Autodesk Inventor part; units mm, degrees
(part 2 of 3)
sketch "Sketch6" plane through (0, 7, 0) normal (0, 1, 0) x (1, 0, 0)
  line L0 (449, 226) -> (-449, 226) projected
  line L1 (-456, 219) -> (-456, -419) projected
  line L2 (456, -419) -> (456, 219) projected
  line L3 (-449, -426) -> (449, -426) projected
  arc A0 (-456, -419) -> (-449, -426) centre (-449, -419) ccw projected
  arc A1 (449, -426) -> (456, -419) centre (449, -419) ccw projected
  arc A2 (456, 219) -> (449, 226) centre (449, 219) ccw projected
  arc A3 (-449, 226) -> (-456, 219) centre (-449, 219) ccw projected
  line L4 (-449, 219) -> (449, 219)
  line L5 (449, 219) -> (449, -419)
  line L6 (449, -419) -> (-449, -419)
  line L7 (-449, -419) -> (-449, 219)
  line L8 (-449, 226) -> (-456, 226)
  line L9 (-456, 226) -> (-456, 219)
  line L10 (449, 226) -> (456, 226)
  line L11 (456, 226) -> (456, 219)
  line L12 (456, -419) -> (456, -426)
  line L13 (456, -426) -> (449, -426)
  line L14 (-456, -419) -> (-456, -426)
  line L15 (-456, -426) -> (-449, -426)
  line L16 (-456, 226) -> (-407.85, 226)
  line L17 (-407.85, 226) -> (-407.85, 219)
  line L18 (-407.85, 219) -> (-456, 219)
  line L19 (-456, 219) -> (-456, 226)
  line L20 (-407.85, 226) -> (-360.15, 226)
  line L21 (-360.15, 226) -> (-360.15, 219)
  line L22 (-360.15, 219) -> (-407.85, 219)
  line L23 (-407.85, 219) -> (-407.85, 226)
  line L24 (-264.15, 226) -> (-264.15, 219)
  line L25 (-311.85, 226) -> (-311.85, 219)
  line L26 (-168.15, 226) -> (-168.15, 219)
  line L27 (-215.85, 226) -> (-215.85, 219)
  line L28 (-72.15, 226) -> (-72.15, 219)
  line L29 (-119.85, 226) -> (-119.85, 219)
  line L30 (23.85, 226) -> (23.85, 219)
  line L31 (-23.85, 226) -> (-23.85, 219)
  line L32 (119.85, 226) -> (119.85, 219)
  line L33 (72.15, 226) -> (72.15, 219)
  line L34 (215.85, 226) -> (215.85, 219)
  line L35 (168.15, 226) -> (168.15, 219)
  line L36 (311.85, 226) -> (311.85, 219)
  line L37 (264.15, 226) -> (264.15, 219)
  line L38 (407.85, 226) -> (407.85, 219)
  line L39 (360.15, 226) -> (360.15, 219)
  line L40 (-449, -100) -> (456, -100) construction
  line L41 (-407.85, -426) -> (-407.85, -419)
  line L42 (-360.15, -426) -> (-360.15, -419)
  line L43 (-264.15, -426) -> (-264.15, -419)
  line L44 (-311.85, -426) -> (-311.85, -419)
  line L45 (-168.15, -426) -> (-168.15, -419)
  line L46 (-215.85, -426) -> (-215.85, -419)
  line L47 (-72.15, -426) -> (-72.15, -419)
  line L48 (-119.85, -426) -> (-119.85, -419)
  line L49 (23.85, -426) -> (23.85, -419)
  line L50 (-23.85, -426) -> (-23.85, -419)
  line L51 (119.85, -426) -> (119.85, -419)
  line L52 (72.15, -426) -> (72.15, -419)
  line L53 (215.85, -426) -> (215.85, -419)
  line L54 (168.15, -426) -> (168.15, -419)
  line L55 (311.85, -426) -> (311.85, -419)
  line L56 (264.15, -426) -> (264.15, -419)
  line L57 (407.85, -426) -> (407.85, -419)
  line L58 (360.15, -426) -> (360.15, -419)
  line L59 (-456, 226) -> (-449, 226)
  line L60 (-449, 226) -> (-449, 199.77)
  line L61 (-449, 199.77) -> (-456, 199.77)
  line L62 (-456, 199.77) -> (-456, 226)
  line L63 (-449, 199.77) -> (-456, 199.77)
  line L64 (-456, 199.77) -> (-456, 173.99)
  line L65 (-456, 173.99) -> (-449, 173.99)
  line L66 (-449, 173.99) -> (-449, 199.77)
  line L67 (-449, 147.61) -> (-456, 147.61)
  line L68 (-456, 121.83) -> (-449, 121.83)
  line L69 (-449, 95.45) -> (-456, 95.45)
  line L70 (-456, 69.67) -> (-449, 69.67)
  line L71 (-449, 43.29) -> (-456, 43.29)
  line L72 (-456, 17.51) -> (-449, 17.51)
  line L73 (-449, -8.87) -> (-456, -8.87)
  line L74 (-456, -34.65) -> (-449, -34.65)
  line L75 (-449, -61.03) -> (-456, -61.03)
  line L76 (-456, -86.81) -> (-449, -86.81)
  line L77 (-449, -113.19) -> (-456, -113.19)
  line L78 (-456, -138.97) -> (-449, -138.97)
  line L79 (-449, -165.35) -> (-456, -165.35)
  line L80 (-456, -191.13) -> (-449, -191.13)
  line L81 (-449, -217.51) -> (-456, -217.51)
  line L82 (-456, -243.29) -> (-449, -243.29)
  line L83 (-449, -269.67) -> (-456, -269.67)
  line L84 (-456, -295.45) -> (-449, -295.45)
  line L85 (-449, -321.83) -> (-456, -321.83)
  line L86 (-456, -347.61) -> (-449, -347.61)
  line L87 (-449, -373.99) -> (-456, -373.99)
  line L88 (-456, -399.77) -> (-449, -399.77)
  line L89 (0, 226) -> (0, -426) construction
  line L90 (449, 199.77) -> (456, 199.77)
  line L91 (456, 173.99) -> (449, 173.99)
  line L92 (449, 147.61) -> (456, 147.61)
  line L93 (456, 121.83) -> (449, 121.83)
  line L94 (449, 95.45) -> (456, 95.45)
  line L95 (456, 69.67) -> (449, 69.67)
  line L96 (449, 43.29) -> (456, 43.29)
  line L97 (456, 17.51) -> (449, 17.51)
  line L98 (449, -8.87) -> (456, -8.87)
  line L99 (456, -34.65) -> (449, -34.65)
  line L100 (449, -61.03) -> (456, -61.03)
  line L101 (456, -86.81) -> (449, -86.81)
  line L102 (449, -113.19) -> (456, -113.19)
  line L103 (456, -138.97) -> (449, -138.97)
  line L104 (449, -165.35) -> (456, -165.35)
  line L105 (456, -191.13) -> (449, -191.13)
  line L106 (449, -217.51) -> (456, -217.51)
  line L107 (456, -243.29) -> (449, -243.29)
  line L108 (449, -269.67) -> (456, -269.67)
  line L109 (456, -295.45) -> (449, -295.45)
  line L110 (449, -321.83) -> (456, -321.83)
  line L111 (456, -347.61) -> (449, -347.61)
  line L112 (449, -373.99) -> (456, -373.99)
  line L113 (456, -399.77) -> (449, -399.77)
  point P0 (0, 0)
  dimension "d424" = 7
  dimension "d425" = 912
  dimension "d426" = 652
  dimension "d427" = 48.15
  dimension "d428" = 47.7
  dimension "d431" = 96
  dimension "d436" = 26.23
  dimension "d437" = 25.78
  dimension "d440" = 52.16
  constraints: 212 end point, 84 symmetric about line, 46 parallel, 44 vertical alignment, 32 horizontal alignment, 7 perpendicular, 6 tangent, 5 horizontal, 2 point on line, 2 vertical, 24 other
  measures "d425" distance of L10.end L8.end
  measures "d426" distance of L12.end L10.end
  measures "d427" distance of L17.end L18.end
  measures "d428" distance between parallel lines of L17 L21
  measures "d431" distance of L20.end L24.start
  measures "d436" distance between parallel lines of L8 L61
  measures "d437" distance between parallel lines of L61 L65
  measures "d440" distance of L60.end L67.start
extrude "Extrusion8" cut sketch "Sketch6" against normal through all contours A2 L2 L90 L5 L4 L38 L0 | L39 L4 L36 L0 | L2 L92 L5 L91 | L37 L4 L34 L0 | L2 L94 L5 L93 | L35 L4 L32 L0 | L2 L96 L5 L95 | L33 L4 L30 L0 | L2 L98 L5 L97 | L31 L4 L28 L0 | L2 L100 L5 L99 | L29 L4 L26 L0 | L2 L102 L5 L101 | L27 L4 L24 L0 | L2 L104 L5 L103 | L25 L4 L21 L0 | L2 L106 L5 L105 | L17 L4 L60 L0 | L60 L18 A3 | L2 L108 L5 L107 | L18 L7 L61 L1 | L2 L110 L5 L109 | L65 L7 L67 L1 | L2 L112 L5 L111 | L68 L7 L69 L1 | L2 A1 L3 L57 L6 L5 L113 | L70 L7 L71 L1 | L72 L7 L73 L1 | L3 L55 L6 L58 | L74 L7 L75 L1 | L3 L53 L6 L56 | L76 L7 L77 L1 | L3 L51 L6 L54 | L78 L7 L79 L1 | L3 L49 L6 L52 | L80 L7 L81 L1 | L3 L47 L6 L50 | L82 L7 L83 L1 | L3 L45 L6 L48 | L84 L7 L85 L1 | L3 L43 L6 L46 | L86 L7 L87 L1 | L3 L42 L6 L44 | L88 L7 L6 L41 L3 A0 L1
fillet "Fillet2" radius 7 4 edges at (449, 3.5, -219) (449, 3.5, 419) (-449, 3.5, -219) (-449, 3.5, 419)
sketch "Sketch8" plane through (0, 7, 0) normal (0, 1, 0) x (1, 0, 0)
  circle A0 centre (126, -281.2169) radius 1.6 projected
  circle A1 centre (36.5, -281.7169) radius 1.575 projected
  circle A2 centre (127, -371.2169) radius 1.575 projected
  circle A3 centre (35.5, -371.2169) radius 1.575 projected
  circle A4 centre (8.08, -301.5) radius 1 projected
  circle A5 centre (-51, -301.5) radius 1 projected
  circle A6 centre (-51, -374.5) radius 1 projected
  circle A7 centre (8.08, -374.5) radius 1 projected
  circle A8 centre (-107.9098, -322.9439) radius 1.75 projected
  circle A9 centre (-145.2893, -322.9439) radius 1.75 projected
  circle A10 centre (-145.2893, -359.6857) radius 1.75 projected
  circle A11 centre (-107.9098, -359.6857) radius 1.75 projected
  arc A12 (-172.603, -348.9) -> (-172.603, -353.4) centre (-172.603, -351.15) ccw projected
  arc A13 (-259.703, -353.4) -> (-259.703, -348.9) centre (-259.703, -351.15) ccw projected
  line L0 (-259.703, -353.4) -> (-264.153, -353.4) projected
  line L1 (-259.703, -348.9) -> (-264.153, -348.9) projected
  arc A14 (-294.103, -348.9) -> (-294.103, -353.4) centre (-294.103, -351.15) ccw projected
  line L2 (-289.653, -348.9) -> (-294.103, -348.9) projected
  line L3 (-294.103, -353.4) -> (-289.653, -353.4) projected
  line L4 (-168.153, -348.9) -> (-172.603, -348.9) projected
  line L5 (-172.603, -353.4) -> (-168.153, -353.4) projected
  line L6 (-381.203, -348.9) -> (-385.653, -348.9) projected
  arc A15 (-381.203, -353.4) -> (-381.203, -348.9) centre (-381.203, -351.15) ccw projected
  line L7 (-381.203, -353.4) -> (-385.653, -353.4) projected
  line L8 (-264.153, -348.9) -> (-264.153, -353.4)
  line L9 (-289.653, -353.4) -> (-289.653, -348.9)
  line L10 (-168.153, -348.9) -> (-168.153, -353.4)
  line L11 (-385.653, -348.9) -> (-385.653, -353.4)
  circle A16 centre (11, -29.5) radius 2.5 projected
  circle A17 centre (11, 29.5) radius 2.5 projected
  circle A18 centre (276, 65.5) radius 2 projected
  circle A19 centre (256, 65.5) radius 2 projected
  point P0 (0, 0)
  constraints: 8 end point, 2 parallel, 2 vertical
extrude "Extrusion9" cut sketch "Sketch8" against normal through all
sketch "Sketch9" plane through (0, 7, 0) normal (0, 1, 0) x (1, 0, 0)
  line L0 (-456, 95.45) -> (-456, 69.67) projected
  line L1 (-456, 89) -> (456, 89)
  line L2 (456, 69.67) -> (456, 95.45) projected
  line L3 (407.85, 226) -> (360.15, 226) projected
  line L4 (456, 69.67) -> (456, 95.45) projected
  line L5 (-456, 82) -> (456, 82)
  line L6 (-449, 89) -> (-449, 82)
  line L7 (-449, 121.83) -> (-449, 95.45) projected
  line L8 (449, 82) -> (449, 89)
  line L9 (449, 95.45) -> (449, 121.83) projected
  line L10 (449, 82) -> (413.08, 82)
  line L11 (413.08, 82) -> (413.08, 89)
  line L12 (413.08, 89) -> (449, 89)
  line L13 (449, 89) -> (449, 82)
  line L14 (377.16, 82) -> (377.16, 89)
  line L15 (341.24, 82) -> (341.24, 89)
  line L16 (305.32, 82) -> (305.32, 89)
  line L17 (269.4, 82) -> (269.4, 89)
  line L18 (233.48, 82) -> (233.48, 89)
  line L19 (197.56, 82) -> (197.56, 89)
  line L20 (161.64, 82) -> (161.64, 89)
  line L21 (125.72, 82) -> (125.72, 89)
  line L22 (89.8, 82) -> (89.8, 89)
  line L23 (53.88, 82) -> (53.88, 89)
  line L24 (17.96, 82) -> (17.96, 89)
  line L25 (-17.96, 82) -> (-17.96, 89)
  line L26 (-53.88, 82) -> (-53.88, 89)
  line L27 (-89.8, 82) -> (-89.8, 89)
  line L28 (-125.72, 82) -> (-125.72, 89)
  line L29 (-161.64, 82) -> (-161.64, 89)
  line L30 (-197.56, 82) -> (-197.56, 89)
  line L31 (-233.48, 82) -> (-233.48, 89)
  line L32 (-269.4, 82) -> (-269.4, 89)
  line L33 (-305.32, 82) -> (-305.32, 89)
  line L34 (-341.24, 82) -> (-341.24, 89)
  line L35 (-377.16, 82) -> (-377.16, 89)
  line L36 (-413.08, 82) -> (-413.08, 89)
  line L37 (-449, 82) -> (-449, 89)
  line L38 (449, -189) -> (-449, -189)
  line L39 (-449, -189) -> (-449, -182)
  line L40 (-449, -182) -> (449, -182)
  line L41 (449, -182) -> (449, -189)
  line L42 (-449, -191.13) -> (-449, -217.51) projected
  line L43 (449, -217.51) -> (449, -191.13) projected
  line L44 (360.15, -426) -> (407.85, -426) projected
  line L45 (449, -189) -> (413.08, -189)
  line L46 (413.08, -189) -> (413.08, -182)
  line L47 (413.08, -182) -> (449, -182)
  line L48 (449, -182) -> (449, -189)
  line L49 (377.16, -189) -> (377.16, -182)
  line L50 (341.24, -189) -> (341.24, -182)
  line L51 (305.32, -189) -> (305.32, -182)
  line L52 (269.4, -189) -> (269.4, -182)
  line L53 (233.48, -189) -> (233.48, -182)
  line L54 (197.56, -189) -> (197.56, -182)
  line L55 (161.64, -189) -> (161.64, -182)
  line L56 (125.72, -189) -> (125.72, -182)
  line L57 (89.8, -189) -> (89.8, -182)
  line L58 (53.88, -189) -> (53.88, -182)
  line L59 (17.96, -189) -> (17.96, -182)
  line L60 (-17.96, -189) -> (-17.96, -182)
  line L61 (-53.88, -189) -> (-53.88, -182)
  line L62 (-89.8, -189) -> (-89.8, -182)
  line L63 (-125.72, -189) -> (-125.72, -182)
  line L64 (-161.64, -189) -> (-161.64, -182)
  line L65 (-197.56, -189) -> (-197.56, -182)
  line L66 (-233.48, -189) -> (-233.48, -182)
  line L67 (-269.4, -189) -> (-269.4, -182)
  line L68 (-305.32, -189) -> (-305.32, -182)
  line L69 (-341.24, -189) -> (-341.24, -182)
  line L70 (-377.16, -189) -> (-377.16, -182)
  line L71 (-413.08, -189) -> (-413.08, -182)
  line L72 (-449, -189) -> (-449, -182)
  point P0 (0, 0)
  point P1 (-449, 85.5)
  point P2 (-449, 108.64)
  point P3 (449, 85.5)
  point P4 (449, 108.64)
  point P5 (-449, -204.32)
  point P6 (-449, -185.5)
  point P7 (449, -185.5)
  point P8 (449, -204.32)
  dimension "d503" = 7
  dimension "d512" = 7
  dimension "d502" = 137
  dimension "d504" = 35.92
  dimension "d507" = 35.92
  dimension "d513" = 237
  dimension "d514" = 35.92
  dimension "d517" = 35.92
  constraints: 120 end point, 96 horizontal alignment, 53 parallel, 8 midpoint, 4 vertical, 4 vertical alignment, 2 horizontal, 2 perpendicular, 2 point on line, 18 other
  measures "d504" distance of L11.end L12.end
  measures "d507" distance of L10.end L14.start
  measures "d514" distance of L46.end L47.end
  measures "d517" distance of L45.end L49.start
extrude "Extrusion10" cut sketch "Sketch9" against normal through all contours L1 L36 L5 L6 | L1 L34 L5 L35 | L1 L32 L5 L33 | L1 L30 L5 L31 | L1 L28 L5 L29 | L1 L26 L5 L27 | L1 L24 L5 L25 | L1 L22 L5 L23 | L1 L20 L5 L21 | L1 L18 L5 L19 | L1 L16 L5 L17 | L1 L14 L5 L15 | L1 L8 L5 L11 | L38 L46 L40 L41 | L38 L50 L40 L49 | L38 L52 L40 L51 | L38 L54 L40 L53 | L38 L56 L40 L55 | L38 L58 L40 L57 | L38 L60 L40 L59 | L38 L62 L40 L61 | L38 L64 L40 L63 | L38 L66 L40 L65 | L38 L68 L40 L67 | L38 L70 L40 L69 | L38 L39 L40 L71
sketch "Sketch10" plane through (0, 7, 0) normal (0, 1, 0) x (1, 0, 0)
  line L0 (269.4, -182) -> (269.4, -189) projected
  line L1 (269.4, -189) -> (305.32, -189) projected
  line L2 (305.32, -189) -> (305.32, -182) projected
  line L3 (305.32, -182) -> (269.4, -182) projected
  line L4 (-17.96, -182) -> (-17.96, -189) projected
  line L5 (-17.96, -189) -> (17.96, -189) projected
  line L6 (17.96, -189) -> (17.96, -182) projected
  line L7 (17.96, -182) -> (-17.96, -182) projected
  line L8 (-305.32, -182) -> (-305.32, -189) projected
  line L9 (-305.32, -189) -> (-269.4, -189) projected
  line L10 (-269.4, -189) -> (-269.4, -182) projected
  line L11 (-269.4, -182) -> (-305.32, -182) projected
  line L12 (341.24, 89) -> (341.24, 82) projected
  line L13 (341.24, 82) -> (377.16, 82) projected
  line L14 (377.16, 82) -> (377.16, 89) projected
  line L15 (377.16, 89) -> (341.24, 89) projected
  line L16 (53.88, 89) -> (53.88, 82) projected
  line L17 (53.88, 82) -> (89.8, 82) projected
  line L18 (89.8, 82) -> (89.8, 89) projected
  line L19 (89.8, 89) -> (53.88, 89) projected
  line L20 (-233.48, 89) -> (-233.48, 82) projected
  line L21 (-233.48, 82) -> (-197.56, 82) projected
  line L22 (-197.56, 82) -> (-197.56, 89) projected
  line L23 (-197.56, 89) -> (-233.48, 89) projected
  line L24 (-413.08, 82) -> (-413.08, 89) projected
  line L25 (-413.08, 89) -> (-449, 89) projected
  line L26 (-449, 89) -> (-449, 82) projected
  line L27 (-449, 82) -> (-413.08, 82) projected
  line L28 (-161.64, 89) -> (-161.64, 82) projected
  line L29 (-161.64, 82) -> (-125.72, 82) projected
  line L30 (-125.72, 82) -> (-125.72, 89) projected
  line L31 (-125.72, 89) -> (-161.64, 89) projected
  line L32 (125.72, 89) -> (125.72, 82) projected
  line L33 (125.72, 82) -> (161.64, 82) projected
  line L34 (161.64, 82) -> (161.64, 89) projected
  line L35 (161.64, 89) -> (125.72, 89) projected
  line L36 (413.08, 89) -> (413.08, 82) projected
  line L37 (413.08, 82) -> (449, 82) projected
  line L38 (449, 82) -> (449, 89) projected
  line L39 (449, 89) -> (413.08, 89) projected
  line L40 (-233.48, -182) -> (-233.48, -189) projected
  line L41 (-233.48, -189) -> (-197.56, -189) projected
  line L42 (-197.56, -189) -> (-197.56, -182) projected
  line L43 (-197.56, -182) -> (-233.48, -182) projected
  line L44 (53.88, -182) -> (53.88, -189) projected
  line L45 (53.88, -189) -> (89.8, -189) projected
  line L46 (89.8, -189) -> (89.8, -182) projected
  line L47 (89.8, -182) -> (53.88, -182) projected
  line L48 (341.24, -182) -> (341.24, -189) projected
  line L49 (341.24, -189) -> (377.16, -189) projected
  line L50 (377.16, -189) -> (377.16, -182) projected
  line L51 (377.16, -182) -> (341.24, -182) projected
  line L52 (197.56, -182) -> (197.56, -189) projected
  line L53 (197.56, -189) -> (233.48, -189) projected
  line L54 (233.48, -189) -> (233.48, -182) projected
  line L55 (233.48, -182) -> (197.56, -182) projected
  line L56 (-89.8, -182) -> (-89.8, -189) projected
  line L57 (-89.8, -189) -> (-53.88, -189) projected
  line L58 (-53.88, -189) -> (-53.88, -182) projected
  line L59 (-53.88, -182) -> (-89.8, -182) projected
  line L60 (-377.16, -182) -> (-377.16, -189) projected
  line L61 (-377.16, -189) -> (-341.24, -189) projected
  line L62 (-341.24, -189) -> (-341.24, -182) projected
  line L63 (-341.24, -182) -> (-377.16, -182) projected
  line L64 (269.4, 89) -> (269.4, 82) projected
  line L65 (269.4, 82) -> (305.32, 82) projected
  line L66 (305.32, 82) -> (305.32, 89) projected
  line L67 (305.32, 89) -> (269.4, 89) projected
  line L68 (-17.96, 89) -> (-17.96, 82) projected
  line L69 (-17.96, 82) -> (17.96, 82) projected
  line L70 (17.96, 82) -> (17.96, 89) projected
  line L71 (17.96, 89) -> (-17.96, 89) projected
  line L72 (-305.32, 89) -> (-305.32, 82) projected
  line L73 (-305.32, 82) -> (-269.4, 82) projected
  line L74 (-269.4, 82) -> (-269.4, 89) projected
  line L75 (-269.4, 89) -> (-305.32, 89) projected
  line L76 (-377.16, 89) -> (-377.16, 82) projected
  line L77 (-377.16, 82) -> (-341.24, 82) projected
  line L78 (-341.24, 82) -> (-341.24, 89) projected
  line L79 (-341.24, 89) -> (-377.16, 89) projected
  line L80 (-89.8, 89) -> (-89.8, 82) projected
  line L81 (-89.8, 82) -> (-53.88, 82) projected
  line L82 (-53.88, 82) -> (-53.88, 89) projected
  line L83 (-53.88, 89) -> (-89.8, 89) projected
  line L84 (197.56, 89) -> (197.56, 82) projected
  line L85 (197.56, 82) -> (233.48, 82) projected
  line L86 (233.48, 82) -> (233.48, 89) projected
  line L87 (233.48, 89) -> (197.56, 89) projected
  line L88 (-413.08, -189) -> (-413.08, -182) projected
  line L89 (-413.08, -182) -> (-449, -182) projected
  line L90 (-449, -182) -> (-449, -189) projected
  line L91 (-449, -189) -> (-413.08, -189) projected
  line L92 (-161.64, -182) -> (-161.64, -189) projected
  line L93 (-161.64, -189) -> (-125.72, -189) projected
  line L94 (-125.72, -189) -> (-125.72, -182) projected
  line L95 (-125.72, -182) -> (-161.64, -182) projected
  line L96 (125.72, -182) -> (125.72, -189) projected
  line L97 (125.72, -189) -> (161.64, -189) projected
  line L98 (161.64, -189) -> (161.64, -182) projected
  line L99 (161.64, -182) -> (125.72, -182) projected
  line L100 (413.08, -182) -> (413.08, -189) projected
  line L101 (413.08, -189) -> (449, -189) projected
  line L102 (449, -189) -> (449, -182) projected
  line L103 (449, -182) -> (413.08, -182) projected
  circle A0 centre (127, -371.2169) radius 1.575 projected
  circle A1 centre (8.08, -374.5) radius 1 projected
  circle A2 centre (-107.9098, -359.6857) radius 1.75 projected
  line L104 (-168.153, -348.9) -> (-172.603, -348.9) projected
  arc A3 (-172.603, -348.9) -> (-172.603, -353.4) centre (-172.603, -351.15) ccw projected
  line L105 (-172.603, -353.4) -> (-168.153, -353.4) projected
  line L106 (-168.153, -353.4) -> (-168.153, -348.9) projected
  arc A4 (-381.203, -353.4) -> (-381.203, -348.9) centre (-381.203, -351.15) ccw projected
  line L107 (-381.203, -348.9) -> (-385.653, -348.9) projected
  line L108 (-385.653, -348.9) -> (-385.653, -353.4) projected
  line L109 (-385.653, -353.4) -> (-381.203, -353.4) projected
  circle A5 centre (-145.2893, -359.6857) radius 1.75 projected
  circle A6 centre (-51, -374.5) radius 1 projected
  circle A7 centre (35.5, -371.2169) radius 1.575 projected
  circle A8 centre (11, 29.5) radius 2.5 projected
  circle A9 centre (126, -281.2169) radius 1.6 projected
  circle A10 centre (8.08, -301.5) radius 1 projected
  circle A11 centre (-107.9098, -322.9439) radius 1.75 projected
  arc A12 (-259.703, -353.4) -> (-259.703, -348.9) centre (-259.703, -351.15) ccw projected
  line L110 (-259.703, -348.9) -> (-264.153, -348.9) projected
  line L111 (-264.153, -348.9) -> (-264.153, -353.4) projected
  line L112 (-264.153, -353.4) -> (-259.703, -353.4) projected
  arc A13 (-294.103, -348.9) -> (-294.103, -353.4) centre (-294.103, -351.15) ccw projected
  line L113 (-294.103, -353.4) -> (-289.653, -353.4) projected
  line L114 (-289.653, -353.4) -> (-289.653, -348.9) projected
  line L115 (-289.653, -348.9) -> (-294.103, -348.9) projected
  circle A14 centre (-145.2893, -322.9439) radius 1.75 projected
  circle A15 centre (-51, -301.5) radius 1 projected
  circle A16 centre (36.5, -281.7169) radius 1.575 projected
  circle A17 centre (11, -29.5) radius 2.5 projected
  line L116 (-407.85, 219) -> (-407.85, 226) projected
  line L117 (-407.85, 226) -> (-360.15, 226) projected
  line L118 (-360.15, 226) -> (-360.15, 219) projected
  line L119 (-360.15, 219) -> (-311.85, 219) projected
  line L120 (-311.85, 219) -> (-311.85, 226) projected
  line L121 (-311.85, 226) -> (-264.15, 226) projected
  line L122 (-264.15, 226) -> (-264.15, 219) projected
  line L123 (-264.15, 219) -> (-215.85, 219) projected
  line L124 (-215.85, 219) -> (-215.85, 226) projected
  line L125 (-215.85, 226) -> (-168.15, 226) projected
  line L126 (-168.15, 226) -> (-168.15, 219) projected
  line L127 (-168.15, 219) -> (-119.85, 219) projected
  line L128 (-119.85, 219) -> (-119.85, 226) projected
  line L129 (-119.85, 226) -> (-72.15, 226) projected
  line L130 (-72.15, 226) -> (-72.15, 219) projected
  line L131 (-72.15, 219) -> (-23.85, 219) projected
  line L132 (-23.85, 219) -> (-23.85, 226) projected
  line L133 (-23.85, 226) -> (23.85, 226) projected
  line L134 (23.85, 226) -> (23.85, 219) projected
  line L135 (23.85, 219) -> (72.15, 219) projected
  line L136 (72.15, 219) -> (72.15, 226) projected
  line L137 (72.15, 226) -> (119.85, 226) projected
  line L138 (119.85, 226) -> (119.85, 219) projected
  line L139 (119.85, 219) -> (168.15, 219) projected
  line L140 (168.15, 219) -> (168.15, 226) projected
  line L141 (168.15, 226) -> (215.85, 226) projected
  line L142 (215.85, 226) -> (215.85, 219) projected
  line L143 (215.85, 219) -> (264.15, 219) projected
  line L144 (264.15, 219) -> (264.15, 226) projected
  line L145 (264.15, 226) -> (311.85, 226) projected
  line L146 (311.85, 226) -> (311.85, 219) projected
  line L147 (311.85, 219) -> (360.15, 219) projected
  line L148 (360.15, 219) -> (360.15, 226) projected
  line L149 (360.15, 226) -> (407.85, 226) projected
  line L150 (407.85, 226) -> (407.85, 219) projected
  line L151 (407.85, 219) -> (442, 219) projected
  arc A18 (449, 212) -> (442, 219) centre (442, 212) ccw projected
  line L152 (449, 212) -> (449, 199.77) projected
  line L153 (449, 199.77) -> (456, 199.77) projected
  line L154 (456, 199.77) -> (456, 173.99) projected
  line L155 (456, 173.99) -> (449, 173.99) projected
  line L156 (449, 173.99) -> (449, 147.61) projected
  line L157 (449, 147.61) -> (456, 147.61) projected
  line L158 (456, 147.61) -> (456, 121.83) projected
  line L159 (456, 121.83) -> (449, 121.83) projected
  line L160 (449, 121.83) -> (449, 95.45) projected
  line L161 (449, 95.45) -> (456, 95.45) projected
  line L162 (456, 95.45) -> (456, 69.67) projected
  line L163 (456, 69.67) -> (449, 69.67) projected
  line L164 (449, 69.67) -> (449, 43.29) projected
  line L165 (449, 43.29) -> (456, 43.29) projected
  line L166 (456, 43.29) -> (456, 17.51) projected
  line L167 (456, 17.51) -> (449, 17.51) projected
  line L168 (449, 17.51) -> (449, -8.87) projected
  line L169 (449, -8.87) -> (456, -8.87) projected
  line L170 (456, -8.87) -> (456, -34.65) projected
  line L171 (456, -34.65) -> (449, -34.65) projected
  line L172 (449, -34.65) -> (449, -61.03) projected
  line L173 (449, -61.03) -> (456, -61.03) projected
  line L174 (456, -61.03) -> (456, -86.81) projected
  line L175 (456, -86.81) -> (449, -86.81) projected
  line L176 (449, -86.81) -> (449, -113.19) projected
  line L177 (449, -113.19) -> (456, -113.19) projected
  line L178 (456, -113.19) -> (456, -138.97) projected
  line L179 (456, -138.97) -> (449, -138.97) projected
  line L180 (449, -138.97) -> (449, -165.35) projected
  line L181 (449, -165.35) -> (456, -165.35) projected
  line L182 (456, -165.35) -> (456, -191.13) projected
  line L183 (456, -191.13) -> (449, -191.13) projected
  line L184 (449, -191.13) -> (449, -217.51) projected
  line L185 (449, -217.51) -> (456, -217.51) projected
  line L186 (456, -217.51) -> (456, -243.29) projected
  line L187 (456, -243.29) -> (449, -243.29) projected
  line L188 (449, -243.29) -> (449, -269.67) projected
  line L189 (449, -269.67) -> (456, -269.67) projected
  line L190 (456, -269.67) -> (456, -295.45) projected
  line L191 (456, -295.45) -> (449, -295.45) projected
  line L192 (449, -295.45) -> (449, -321.83) projected
  line L193 (449, -321.83) -> (456, -321.83) projected
  line L194 (456, -321.83) -> (456, -347.61) projected
  line L195 (456, -347.61) -> (449, -347.61) projected
  line L196 (449, -347.61) -> (449, -373.99) projected
  line L197 (449, -373.99) -> (456, -373.99) projected
  line L198 (456, -373.99) -> (456, -399.77) projected
  line L199 (456, -399.77) -> (449, -399.77) projected
  line L200 (449, -399.77) -> (449, -412) projected
  arc A19 (442, -419) -> (449, -412) centre (442, -412) ccw projected
  line L201 (442, -419) -> (407.85, -419) projected
  line L202 (407.85, -419) -> (407.85, -426) projected
  line L203 (407.85, -426) -> (360.15, -426) projected
  line L204 (360.15, -426) -> (360.15, -419) projected
  line L205 (360.15, -419) -> (311.85, -419) projected
  line L206 (311.85, -419) -> (311.85, -426) projected
  line L207 (311.85, -426) -> (264.15, -426) projected
  line L208 (264.15, -426) -> (264.15, -419) projected
  line L209 (264.15, -419) -> (215.85, -419) projected
  line L210 (215.85, -419) -> (215.85, -426) projected
  line L211 (215.85, -426) -> (168.15, -426) projected
  line L212 (168.15, -426) -> (168.15, -419) projected
  line L213 (168.15, -419) -> (119.85, -419) projected
  line L214 (119.85, -419) -> (119.85, -426) projected
  line L215 (119.85, -426) -> (72.15, -426) projected
  line L216 (72.15, -426) -> (72.15, -419) projected
  line L217 (72.15, -419) -> (23.85, -419) projected
  line L218 (23.85, -419) -> (23.85, -426) projected
  line L219 (23.85, -426) -> (-23.85, -426) projected
  line L220 (-23.85, -426) -> (-23.85, -419) projected
  line L221 (-23.85, -419) -> (-72.15, -419) projected
  line L222 (-72.15, -419) -> (-72.15, -426) projected
  line L223 (-72.15, -426) -> (-119.85, -426) projected
  line L224 (-119.85, -426) -> (-119.85, -419) projected
  line L225 (-119.85, -419) -> (-168.15, -419) projected
  line L226 (-168.15, -419) -> (-168.15, -426) projected
  line L227 (-168.15, -426) -> (-215.85, -426) projected
  line L228 (-215.85, -426) -> (-215.85, -419) projected
  line L229 (-215.85, -419) -> (-264.15, -419) projected
  line L230 (-264.15, -419) -> (-264.15, -426) projected
  line L231 (-264.15, -426) -> (-311.85, -426) projected
  line L232 (-311.85, -426) -> (-311.85, -419) projected
  line L233 (-311.85, -419) -> (-360.15, -419) projected
  line L234 (-360.15, -419) -> (-360.15, -426) projected
  line L235 (-360.15, -426) -> (-407.85, -426) projected
  line L236 (-407.85, -426) -> (-407.85, -419) projected
  line L237 (-407.85, -419) -> (-442, -419) projected
  arc A20 (-449, -412) -> (-442, -419) centre (-442, -412) ccw projected
  line L238 (-449, -412) -> (-449, -399.77) projected
  line L239 (-449, -399.77) -> (-456, -399.77) projected
  line L240 (-456, -399.77) -> (-456, -373.99) projected
  line L241 (-456, -373.99) -> (-449, -373.99) projected
  line L242 (-449, -373.99) -> (-449, -347.61) projected
  line L243 (-449, -347.61) -> (-456, -347.61) projected
  line L244 (-456, -347.61) -> (-456, -321.83) projected
  line L245 (-456, -321.83) -> (-449, -321.83) projected
  line L246 (-449, -321.83) -> (-449, -295.45) projected
  line L247 (-449, -295.45) -> (-456, -295.45) projected
  line L248 (-456, -295.45) -> (-456, -269.67) projected
  line L249 (-456, -269.67) -> (-449, -269.67) projected
  line L250 (-449, -269.67) -> (-449, -243.29) projected
  line L251 (-449, -243.29) -> (-456, -243.29) projected
  line L252 (-456, -243.29) -> (-456, -217.51) projected
  line L253 (-456, -217.51) -> (-449, -217.51) projected
  line L254 (-449, -217.51) -> (-449, -191.13) projected
  line L255 (-449, -191.13) -> (-456, -191.13) projected
  line L256 (-456, -191.13) -> (-456, -165.35) projected
  line L257 (-456, -165.35) -> (-449, -165.35) projected
  line L258 (-449, -165.35) -> (-449, -138.97) projected
  line L259 (-449, -138.97) -> (-456, -138.97) projected
  line L260 (-456, -138.97) -> (-456, -113.19) projected
  line L261 (-456, -113.19) -> (-449, -113.19) projected
  line L262 (-449, -113.19) -> (-449, -86.81) projected
  line L263 (-449, -86.81) -> (-456, -86.81) projected
  line L264 (-456, -86.81) -> (-456, -61.03) projected
  line L265 (-456, -61.03) -> (-449, -61.03) projected
  line L266 (-449, -61.03) -> (-449, -34.65) projected
  line L267 (-449, -34.65) -> (-456, -34.65) projected
  line L268 (-456, -34.65) -> (-456, -8.87) projected
  line L269 (-456, -8.87) -> (-449, -8.87) projected
  line L270 (-449, -8.87) -> (-449, 17.51) projected
  line L271 (-449, 17.51) -> (-456, 17.51) projected
  line L272 (-456, 17.51) -> (-456, 43.29) projected
  line L273 (-456, 43.29) -> (-449, 43.29) projected
  line L274 (-449, 43.29) -> (-449, 69.67) projected
  line L275 (-449, 69.67) -> (-456, 69.67) projected
  line L276 (-456, 69.67) -> (-456, 95.45) projected
  line L277 (-456, 95.45) -> (-449, 95.45) projected
  line L278 (-449, 95.45) -> (-449, 121.83) projected
  line L279 (-449, 121.83) -> (-456, 121.83) projected
  line L280 (-456, 121.83) -> (-456, 147.61) projected
  line L281 (-456, 147.61) -> (-449, 147.61) projected
  line L282 (-449, 147.61) -> (-449, 173.99) projected
  line L283 (-449, 173.99) -> (-456, 173.99) projected
  line L284 (-456, 173.99) -> (-456, 199.77) projected
  line L285 (-456, 199.77) -> (-449, 199.77) projected
  line L286 (-449, 199.77) -> (-449, 212) projected
  arc A21 (-442, 219) -> (-449, 212) centre (-442, 212) ccw projected
  line L287 (-442, 219) -> (-407.85, 219) projected
  line L288 (-376, -308.5) -> (-76, -308.5) projected
  arc A22 (-76, -308.5) -> (-76, -283.5) centre (-76, -296) ccw projected
  line L289 (-76, -283.5) -> (-376, -283.5) projected
  arc A23 (-376, -283.5) -> (-376, -308.5) centre (-376, -296) ccw projected
  line L290 (151.5, -286) -> (151.5, -366) projected
  arc A24 (151.5, -366) -> (176.5, -366) centre (164, -366) ccw projected
  line L291 (176.5, -366) -> (176.5, -286) projected
  arc A25 (176.5, -286) -> (151.5, -286) centre (164, -286) ccw projected
  arc A26 (266, -25) -> (268, -23) centre (266, -23) ccw projected
  line L292 (268, -23) -> (268, 23) projected
  arc A27 (268, 23) -> (266, 25) centre (266, 23) ccw projected
  line L293 (266, 25) -> (107, 25) projected
  arc A28 (107, 25) -> (105, 23) centre (107, 23) ccw projected
  line L294 (105, 23) -> (105, -23) projected
  arc A29 (105, -23) -> (107, -25) centre (107, -23) ccw projected
  line L295 (107, -25) -> (266, -25) projected
  circle A30 centre (354.8, 16) radius 2.9 projected
  circle A31 centre (354.8, -16) radius 2.9 projected
  line L296 (204, -276) -> (201, -276) projected
  line L297 (201, -276) -> (201, -296) projected
  line L298 (201, -296) -> (204, -296) projected
  line L299 (204, -296) -> (204, -276) projected
  line L300 (-423, -316) -> (-426, -316) projected
  line L301 (-426, -316) -> (-426, -336) projected
  line L302 (-426, -336) -> (-423, -336) projected
  line L303 (-423, -336) -> (-423, -316) projected
  line L304 (9, -393) -> (9, -396) projected
  line L305 (9, -396) -> (57, -396) projected
  line L306 (57, -396) -> (57, -393) projected
  line L307 (57, -393) -> (9, -393) projected
  line L308 (-39, -259) -> (-39, -256) projected
  line L309 (-39, -256) -> (-87, -256) projected
  line L310 (-87, -256) -> (-87, -259) projected
  line L311 (-87, -259) -> (-39, -259) projected
  circle A32 centre (-67, 43) radius 2.5 projected
  circle A33 centre (-130, 43) radius 2.5 projected
  line L312 (46.5, 68) -> (51.5, 68) projected
  line L313 (51.5, 68) -> (51.5, 71) projected
  line L314 (51.5, 71) -> (46.5, 71) projected
  line L315 (46.5, 71) -> (46.5, 68) projected
  line L316 (3, 53) -> (6, 53) projected
  line L317 (6, 53) -> (6, 63) projected
  line L318 (6, 63) -> (3, 63) projected
  line L319 (3, 63) -> (3, 53) projected
  line L320 (46.25, -48) -> (56.25, -48) projected
  line L321 (56.25, -48) -> (56.25, -45) projected
  line L322 (56.25, -45) -> (46.25, -45) projected
  line L323 (46.25, -45) -> (46.25, -48) projected
  line L324 (46.25, -78) -> (46.25, -81) projected
  line L325 (46.25, -81) -> (56.25, -81) projected
  line L326 (56.25, -81) -> (56.25, -78) projected
  line L327 (56.25, -78) -> (46.25, -78) projected
  line L328 (61, -119.5) -> (61, -134.5) projected
  line L329 (61, -134.5) -> (64, -134.5) projected
  line L330 (64, -134.5) -> (64, -119.5) projected
  line L331 (64, -119.5) -> (61, -119.5) projected
  arc A34 (-406.25, 176) -> (-406, 176.25) centre (-406.25, 176.25) ccw projected
  line L332 (-406, 176.25) -> (-406, 195.75) projected
  arc A35 (-406, 195.75) -> (-406.25, 196) centre (-406.25, 195.75) ccw projected
  line L333 (-406.25, 196) -> (-425.75, 196) projected
  arc A36 (-425.75, 196) -> (-426, 195.75) centre (-425.75, 195.75) ccw projected
  line L334 (-426, 195.75) -> (-426, 176.25) projected
  arc A37 (-426, 176.25) -> (-425.75, 176) centre (-425.75, 176.25) ccw projected
  line L335 (-425.75, 176) -> (-406.25, 176) projected
  line L336 (-6.25, 196) -> (-25.75, 196) projected
  arc A38 (-25.75, 196) -> (-26, 195.75) centre (-25.75, 195.75) ccw projected
  line L337 (-26, 195.75) -> (-26, 176.25) projected
  arc A39 (-26, 176.25) -> (-25.75, 176) centre (-25.75, 176.25) ccw projected
  line L338 (-25.75, 176) -> (-6.25, 176) projected
  arc A40 (-6.25, 176) -> (-6, 176.25) centre (-6.25, 176.25) ccw projected
  line L339 (-6, 176.25) -> (-6, 195.75) projected
  arc A41 (-6, 195.75) -> (-6.25, 196) centre (-6.25, 195.75) ccw projected
  line L340 (2.5, -233.9) -> (5.5, -233.9) projected
  arc A42 (5.5, -233.9) -> (5.5, -228.1) centre (5.5, -231) ccw projected
  line L341 (5.5, -228.1) -> (2.5, -228.1) projected
  arc A43 (2.5, -228.1) -> (2.5, -233.9) centre (2.5, -231) ccw projected
  line L342 (-397.5, 183.1) -> (-394.5, 183.1) projected
  arc A44 (-394.5, 183.1) -> (-394.5, 188.9) centre (-394.5, 186) ccw projected
  line L343 (-394.5, 188.9) -> (-397.5, 188.9) projected
  arc A45 (-397.5, 188.9) -> (-397.5, 183.1) centre (-397.5, 186) ccw projected
  line L344 (-6.25, -221) -> (-25.75, -221) projected
  arc A46 (-25.75, -221) -> (-26, -221.25) centre (-25.75, -221.25) ccw projected
  line L345 (-26, -221.25) -> (-26, -240.75) projected
  arc A47 (-26, -240.75) -> (-25.75, -241) centre (-25.75, -240.75) ccw projected
  line L346 (-25.75, -241) -> (-6.25, -241) projected
  arc A48 (-6.25, -241) -> (-6, -240.75) centre (-6.25, -240.75) ccw projected
  line L347 (-6, -240.75) -> (-6, -221.25) projected
  arc A49 (-6, -221.25) -> (-6.25, -221) centre (-6.25, -221.25) ccw projected
  line L348 (-397.5, -233.9) -> (-394.5, -233.9) projected
  arc A50 (-394.5, -233.9) -> (-394.5, -228.1) centre (-394.5, -231) ccw projected
  line L349 (-394.5, -228.1) -> (-397.5, -228.1) projected
  arc A51 (-397.5, -228.1) -> (-397.5, -233.9) centre (-397.5, -231) ccw projected
  line L350 (296.0285, -196) -> (296, -196) projected
  line L351 (296, -196) -> (296, -396) projected
  line L352 (296, -396) -> (396, -396) projected
  line L353 (396, -396) -> (396, -395.9955) projected
  line L354 (56.25, -142) -> (46.25, -142) projected
  line L355 (46.25, -142) -> (46.25, -145) projected
  line L356 (46.25, -145) -> (56.25, -145) projected
  line L357 (56.25, -145) -> (56.25, -142) projected
  line L358 (61, -55.5) -> (61, -70.5) projected
  line L359 (61, -70.5) -> (64, -70.5) projected
  line L360 (64, -70.5) -> (64, -55.5) projected
  line L361 (64, -55.5) -> (61, -55.5) projected
  arc A52 (49, -110) -> (44, -105) centre (44, -110) ccw projected
  line L362 (44, -105) -> (24, -105) projected
  arc A53 (24, -105) -> (19, -110) centre (24, -110) ccw projected
  line L363 (19, -110) -> (19, -120) projected
  arc A54 (19, -120) -> (24, -125) centre (24, -120) ccw projected
  line L364 (24, -125) -> (44, -125) projected
  arc A55 (44, -125) -> (49, -120) centre (44, -120) ccw projected
  line L365 (49, -120) -> (49, -110) projected
  line L366 (56, 63) -> (56, 53) projected
  line L367 (56, 53) -> (59, 53) projected
  line L368 (59, 53) -> (59, 63) projected
  line L369 (59, 63) -> (56, 63) projected
  line L370 (37, 62) -> (25, 62) projected
  arc A56 (25, 62) -> (25, 54) centre (25, 58) ccw projected
  line L371 (25, 54) -> (37, 54) projected
  arc A57 (37, 54) -> (37, 62) centre (37, 58) ccw projected
  circle A58 centre (-193, 43) radius 2.5 projected
  circle A59 centre (-67, -88) radius 2.5 projected
  line L372 (-135, -259) -> (-135, -256) projected
  line L373 (-135, -256) -> (-183, -256) projected
  line L374 (-183, -256) -> (-183, -259) projected
  line L375 (-183, -259) -> (-135, -259) projected
  line L376 (105, -393) -> (105, -396) projected
  line L377 (105, -396) -> (153, -396) projected
  line L378 (153, -396) -> (153, -393) projected
  line L379 (153, -393) -> (105, -393) projected
  line L380 (-423, -356) -> (-426, -356) projected
  line L381 (-426, -356) -> (-426, -376) projected
  line L382 (-426, -376) -> (-423, -376) projected
  line L383 (-423, -376) -> (-423, -356) projected
  line L384 (204, -316) -> (201, -316) projected
  line L385 (201, -316) -> (201, -336) projected
  line L386 (201, -336) -> (204, -336) projected
  line L387 (204, -336) -> (204, -316) projected
  line L388 (-279, -393) -> (-279, -396) projected
  line L389 (-279, -396) -> (-231, -396) projected
  line L390 (-231, -396) -> (-231, -393) projected
  line L391 (-231, -393) -> (-279, -393) projected
  line L392 (-423, -276) -> (-426, -276) projected
  line L393 (-426, -276) -> (-426, -296) projected
  line L394 (-426, -296) -> (-423, -296) projected
  line L395 (-423, -296) -> (-423, -276) projected
  line L396 (-87, -393) -> (-87, -396) projected
  line L397 (-87, -396) -> (-39, -396) projected
  line L398 (-39, -396) -> (-39, -393) projected
  line L399 (-39, -393) -> (-87, -393) projected
  line L400 (57, -259) -> (57, -256) projected
  line L401 (57, -256) -> (9, -256) projected
  line L402 (9, -256) -> (9, -259) projected
  line L403 (9, -259) -> (57, -259) projected
  line L404 (-327, -259) -> (-327, -256) projected
  line L405 (-327, -256) -> (-375, -256) projected
  line L406 (-375, -256) -> (-375, -259) projected
  line L407 (-375, -259) -> (-327, -259) projected
  circle A60 centre (-130, -88) radius 2.5 projected
  line L408 (51.5, 48) -> (46.5, 48) projected
  line L409 (46.5, 48) -> (46.5, 45) projected
  line L410 (46.5, 45) -> (51.5, 45) projected
  line L411 (51.5, 45) -> (51.5, 48) projected
  line L412 (15.5, 48) -> (10.5, 48) projected
  line L413 (10.5, 48) -> (10.5, 45) projected
  line L414 (10.5, 45) -> (15.5, 45) projected
  line L415 (15.5, 45) -> (15.5, 48) projected
  circle A61 centre (27.09, -53.5) radius 1.25 projected
  line L416 (11.75, -48) -> (21.75, -48) projected
  line L417 (21.75, -48) -> (21.75, -45) projected
  line L418 (21.75, -45) -> (11.75, -45) projected
  line L419 (11.75, -45) -> (11.75, -48) projected
  line L420 (11.75, -78) -> (11.75, -81) projected
  line L421 (11.75, -81) -> (21.75, -81) projected
  line L422 (21.75, -81) -> (21.75, -78) projected
  line L423 (21.75, -78) -> (11.75, -78) projected
  line L424 (7, -134.5) -> (7, -119.5) projected
  line L425 (7, -119.5) -> (4, -119.5) projected
  line L426 (4, -119.5) -> (4, -134.5) projected
  line L427 (4, -134.5) -> (7, -134.5) projected
  line L428 (-406.25, -221) -> (-425.75, -221) projected
  arc A62 (-425.75, -221) -> (-426, -221.25) centre (-425.75, -221.25) ccw projected
  line L429 (-426, -221.25) -> (-426, -240.75) projected
  arc A63 (-426, -240.75) -> (-425.75, -241) centre (-425.75, -240.75) ccw projected
  line L430 (-425.75, -241) -> (-406.25, -241) projected
  arc A64 (-406.25, -241) -> (-406, -240.75) centre (-406.25, -240.75) ccw projected
  line L431 (-406, -240.75) -> (-406, -221.25) projected
  arc A65 (-406, -221.25) -> (-406.25, -221) centre (-406.25, -221.25) ccw projected
  arc A66 (-37.5, 188.9) -> (-37.5, 183.1) centre (-37.5, 186) ccw projected
  line L432 (-37.5, 183.1) -> (-34.5, 183.1) projected
  arc A67 (-34.5, 183.1) -> (-34.5, 188.9) centre (-34.5, 186) ccw projected
  line L433 (-34.5, 188.9) -> (-37.5, 188.9) projected
  arc A68 (-37.5, -228.1) -> (-37.5, -233.9) centre (-37.5, -231) ccw projected
  line L434 (-37.5, -233.9) -> (-34.5, -233.9) projected
  arc A69 (-34.5, -233.9) -> (-34.5, -228.1) centre (-34.5, -231) ccw projected
  line L435 (-34.5, -228.1) -> (-37.5, -228.1) projected
  arc A70 (-437.5, 188.9) -> (-437.5, 183.1) centre (-437.5, 186) ccw projected
  line L436 (-437.5, 183.1) -> (-434.5, 183.1) projected
  arc A71 (-434.5, 183.1) -> (-434.5, 188.9) centre (-434.5, 186) ccw projected
  line L437 (-434.5, 188.9) -> (-437.5, 188.9) projected
  line L438 (2.5, 183.1) -> (5.5, 183.1) projected
  arc A72 (5.5, 183.1) -> (5.5, 188.9) centre (5.5, 186) ccw projected
  line L439 (5.5, 188.9) -> (2.5, 188.9) projected
  arc A73 (2.5, 188.9) -> (2.5, 183.1) centre (2.5, 186) ccw projected
  arc A74 (-437.5, -228.1) -> (-437.5, -233.9) centre (-437.5, -231) ccw projected
  line L440 (-437.5, -233.9) -> (-434.5, -233.9) projected
  arc A75 (-434.5, -233.9) -> (-434.5, -228.1) centre (-434.5, -231) ccw projected
  line L441 (-434.5, -228.1) -> (-437.5, -228.1) projected
  line L442 (21.75, -142) -> (11.75, -142) projected
  line L443 (11.75, -142) -> (11.75, -145) projected
  line L444 (11.75, -145) -> (21.75, -145) projected
  line L445 (21.75, -145) -> (21.75, -142) projected
  line L446 (7, -70.5) -> (7, -55.5) projected
  line L447 (7, -55.5) -> (4, -55.5) projected
  line L448 (4, -55.5) -> (4, -70.5) projected
  line L449 (4, -70.5) -> (7, -70.5) projected
  circle A76 centre (40.91, -53.5) radius 1.25 projected
  line L450 (29, 51) -> (29, 48) projected
  line L451 (29, 48) -> (33, 48) projected
  line L452 (33, 48) -> (33, 51) projected
  line L453 (33, 51) -> (29, 51) projected
  line L454 (10.5, 68) -> (15.5, 68) projected
  line L455 (15.5, 68) -> (15.5, 71) projected
  line L456 (15.5, 71) -> (10.5, 71) projected
  line L457 (10.5, 71) -> (10.5, 68) projected
  circle A77 centre (-193, -88) radius 2.5 projected
  line L458 (-231, -259) -> (-231, -256) projected
  line L459 (-231, -256) -> (-279, -256) projected
  line L460 (-279, -256) -> (-279, -259) projected
  line L461 (-279, -259) -> (-231, -259) projected
  line L462 (153, -259) -> (153, -256) projected
  line L463 (153, -256) -> (105, -256) projected
  line L464 (105, -256) -> (105, -259) projected
  line L465 (105, -259) -> (153, -259) projected
  line L466 (-183, -393) -> (-183, -396) projected
  line L467 (-183, -396) -> (-135, -396) projected
  line L468 (-135, -396) -> (-135, -393) projected
  line L469 (-135, -393) -> (-183, -393) projected
  line L470 (204, -356) -> (201, -356) projected
  line L471 (201, -356) -> (201, -376) projected
  line L472 (201, -376) -> (204, -376) projected
  line L473 (204, -376) -> (204, -356) projected
  line L474 (-375, -393) -> (-375, -396) projected
  line L475 (-375, -396) -> (-327, -396) projected
  line L476 (-327, -396) -> (-327, -393) projected
  line L477 (-327, -393) -> (-375, -393) projected
  line L478 (359.7411, -371) -> (359.7411, -321) projected
  arc A78 (359.7411, -321) -> (329.7411, -321) centre (344.7411, -321) ccw projected
  line L479 (329.7411, -321) -> (329.7411, -371) projected
  arc A79 (329.7411, -371) -> (359.7411, -371) centre (344.7411, -371) ccw projected
  line L480 (393, -393) -> (353.0285, -393) projected
  line L481 (299.0285, -199) -> (393, -199) projected
  line L482 (393, -199) -> (393, -393) projected
  line L483 (340.5, -108.65) -> (340.5, -88.35) projected
  line L484 (337.5, -88.35) -> (337.5, -108.65) projected
  line L485 (340.5, -88.35) -> (337.5, -88.35) projected
  line L486 (340.5, -108.65) -> (337.5, -108.65) projected
  line L487 (320.65, -122) -> (320.65, -125) projected
  line L488 (300.35, -125) -> (320.65, -125) projected
  line L489 (320.65, -122) -> (300.35, -122) projected
  line L490 (300.35, -122) -> (300.35, -125) projected
  line L491 (275.65, -122) -> (255.35, -122) projected
  line L492 (255.35, -122) -> (255.35, -125) projected
  line L493 (255.35, -125) -> (275.65, -125) projected
  line L494 (275.65, -122) -> (275.65, -125) projected
  line L495 (230.65, -122) -> (230.65, -125) projected
  line L496 (210.35, -125) -> (230.65, -125) projected
  line L497 (230.65, -122) -> (210.35, -122) projected
  line L498 (210.35, -122) -> (210.35, -125) projected
  line L499 (165.35, -122) -> (165.35, -125) projected
  line L500 (185.65, -122) -> (165.35, -122) projected
  line L501 (165.35, -125) -> (185.65, -125) projected
  line L502 (185.65, -122) -> (185.65, -125) projected
  line L503 (143.5, -108.65) -> (140.5, -108.65) projected
  line L504 (143.5, -108.65) -> (143.5, -88.35) projected
  line L505 (140.5, -88.35) -> (140.5, -108.65) projected
  line L506 (143.5, -88.35) -> (140.5, -88.35) projected
  line L507 (143.5, 88.35) -> (143.5, 108.65) projected
  line L508 (140.5, 108.65) -> (140.5, 88.35) projected
  line L509 (143.5, 108.65) -> (140.5, 108.65) projected
  line L510 (143.5, 88.35) -> (140.5, 88.35) projected
  line L511 (185.65, 125) -> (165.35, 125) projected
  line L512 (165.35, 125) -> (165.35, 122) projected
  line L513 (165.35, 122) -> (185.65, 122) projected
  line L514 (185.65, 125) -> (185.65, 122) projected
  line L515 (210.35, 125) -> (210.35, 122) projected
  line L516 (230.65, 125) -> (210.35, 125) projected
  line L517 (210.35, 122) -> (230.65, 122) projected
  line L518 (230.65, 125) -> (230.65, 122) projected
  line L519 (255.35, 125) -> (255.35, 122) projected
  line L520 (255.35, 122) -> (275.65, 122) projected
  line L521 (275.65, 125) -> (255.35, 125) projected
  line L522 (275.65, 125) -> (275.65, 122) projected
  line L523 (300.35, 125) -> (300.35, 122) projected
  line L524 (300.35, 122) -> (320.65, 122) projected
  line L525 (320.65, 125) -> (300.35, 125) projected
  line L526 (320.65, 125) -> (320.65, 122) projected
  line L527 (340.5, 88.35) -> (340.5, 108.65) projected
  line L528 (340.5, 108.65) -> (337.5, 108.65) projected
  line L529 (337.5, 108.65) -> (337.5, 88.35) projected
  line L530 (340.5, 88.35) -> (337.5, 88.35)
  circle A80 centre (256, 65.5) radius 2 projected
  circle A81 centre (276, 65.5) radius 2 projected
  line L531 (396, -395.9955) -> (393.0285, -395.9955) projected
  line L532 (393.0285, -395.9955) -> (393.0285, -356.5955) projected
  line L533 (393.0285, -356.5955) -> (396, -356.5955) projected
  line L534 (396, -356.5955) -> (396, -316.5955) projected
  line L535 (396, -316.5955) -> (393.0285, -316.5955) projected
  line L536 (393.0285, -316.5955) -> (393.0285, -276.2955) projected
  line L537 (393.0285, -276.2955) -> (396, -276.2955) projected
  line L538 (396, -276.2955) -> (396, -236.2955) projected
  line L539 (396, -236.2955) -> (393.0285, -236.2955) projected
  line L540 (393.0285, -236.2955) -> (393.0285, -196) projected
  line L541 (393.0285, -196) -> (353.0285, -196) projected
  line L542 (353.0285, -196) -> (353.0285, -198.9955) projected
  line L543 (353.0285, -198.9955) -> (312.7285, -198.9955) projected
  line L544 (312.7285, -198.9955) -> (312.7285, -196) projected
  line L545 (312.7285, -196) -> (299.0285, -196) projected
  line L546 (299.0285, -196) -> (299.0285, -199) projected
  line L547 (353.0285, -393) -> (353.0285, -395.9955) projected
  line L548 (353.0285, -395.9955) -> (312.7285, -395.9955) projected
  line L549 (312.7285, -395.9955) -> (312.7285, -393) projected
  line L550 (312.7285, -393) -> (299.0285, -393) projected
  line L551 (299.0285, -393) -> (299.0285, -395.9955) projected
  line L552 (299.0285, -395.9955) -> (296.0285, -395.9955) projected
  line L553 (296.0285, -395.9955) -> (296.0285, -356.5955) projected
  line L554 (296.0285, -356.5955) -> (299, -356.5955) projected
  line L555 (299, -356.5955) -> (299, -316.5955) projected
  line L556 (299, -316.5955) -> (296.0285, -316.5955) projected
  line L557 (296.0285, -316.5955) -> (296.0285, -276.2955) projected
  line L558 (296.0285, -276.2955) -> (299, -276.2955) projected
  line L559 (299, -276.2955) -> (299, -236.2955) projected
  line L560 (299, -236.2955) -> (296.0285, -236.2955) projected
  line L561 (296.0285, -236.2955) -> (296.0285, -196) projected
  point P0 (0, 0)
  constraints: 2 end point, 1 horizontal
extrude "Extrusion11" cut sketch "Sketch10" against normal through all contours L508 L509 L507 L35 | L35 L507 L510 L508 | L486 L484 L485 L483 | L487 L488 L490 L489 | L494 L493 L492 L491 | L495 L496 L498 L497 | L500 L502 L501 L499 | L503 L505 L506 L504 | L514 L513 L512 L511 | L516 L518 L517 L515 | L521 L522 L520 L519 | L525 L526 L524 L523 | L530 L529 L528 L527